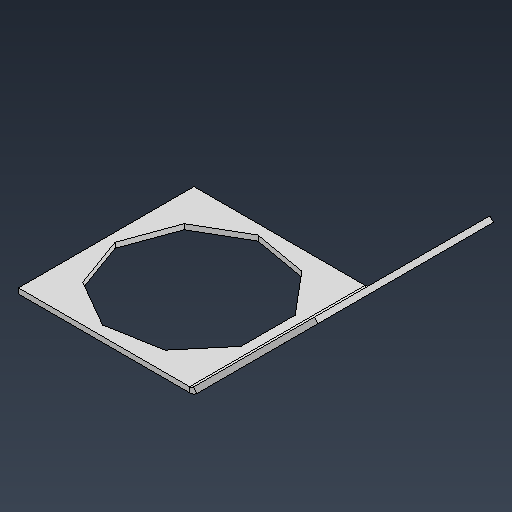
# Autodesk Inventor part: PROJECT_X.0002
Saved by Autodesk Inventor 2026 (Build 300175000, 175)
## iProperties
Manager: Летов
Company: ООО "МОЯ ОБОРОНА"
Created: 2026-10-15
Part Number: PROJECT_X.0002
Material: Типовые
Document SubType Name: Sheet Metal
Designer: dmitrii.kriskovets
Density: 1 g/cm^3
Sheet Metal Rule: По умолчанию_мм
Appearance: По умолчанию
Checked By: Летов
Engr Approved By: Летов
Mfg Approved By: Летов
Authority: Летов
Mass: 41.9969 g
Surface Area: 306.204 cm^2
Volume: 41.9969 cm^3
Flat Pattern Width: 10 cm
Flat Pattern Length: 19.8422 cm
Flat Pattern Area: 198.422 cm^2
Sheet Metal Width: 100,0 мм
Sheet Metal Length: 198,4 мм
Sheet Metal Area: 19842,2 мм^2
Author: Ивлев
Title: Деталь 1
Autodesk Inventor part; units mm, degrees
ref_plane "YZ Plane" through (0, 0, 0) normal (1, 0, 0) x (0, 1, 0)
ref_plane "XZ Plane" through (0, 0, 0) normal (0, 1, 0) x (-1, 0, 0)
ref_plane "XY Plane" through (0, 0, 0) normal (0, 0, 1) x (1, 0, 0)
sketch "Эскиз1" plane through (0, 0, 0) normal (0, 1, 0) x (-1, 0, 0)
  line L0 (-50, 50) -> (50, 50)
  line L1 (50, 50) -> (50, -50)
  line L2 (50, -50) -> (-50, -50)
  line L3 (-50, -50) -> (-50, 50)
  line L4 (-50, 50) -> (50, -50) construction
  line L5 (50, 50) -> (-50, -50) construction
  point P0 (0, 0)
  dimension "d0" = 100
  dimension "d1" = 100
  measures "d0" distance of L0.start L0.end
  measures "d1" distance of L0.end L1.end
extrude "Пластина1" add sketch "Эскиз1" along normal blind 3
sketch "Эскиз2" plane through (0, 3, 0) normal (0, 1, 0) x (1, 0, 0)
  line L0 (-50, -50) -> (-50, 50) construction
  line L1 (50, 50) -> (50, -50) construction
  line L2 (50, -50) -> (-50, -50) construction
  line L3 (-50, 50) -> (50, 50) construction
  line L4 (50, 0) -> (-50, 0)
  line L5 (-45, 0) -> (-34.472, 28.9254)
  line L6 (-34.472, 28.9254) -> (-7.8142, 44.3163)
  line L7 (-7.8142, 44.3163) -> (22.5, 38.9711)
  line L8 (22.5, 38.9711) -> (42.2862, 15.3909)
  line L9 (42.2862, 15.3909) -> (42.2862, -15.3909)
  line L10 (42.2862, -15.3909) -> (22.5, -38.9711)
  line L11 (22.5, -38.9711) -> (-7.8142, -44.3163)
  line L12 (-7.8142, -44.3163) -> (-34.472, -28.9254)
  line L13 (-34.472, -28.9254) -> (-45, 0)
  point P0 (0, 0)
  point P1 (0, 0)
  dimension "d3" = 5
  constraints: 20 end point, 3 midpoint, 1 coincident, 1 point on line, 19 other
  measures "d3" distance of point (-50, 0) L5.start
extrude "Выдавливание1" cut sketch "Эскиз2" against normal blind 10
sketch "Эскиз3" plane through (47.8787, 2.1213, -50) normal (0.7071068, -0.7071068, 0) x (0.7071068, 0.7071068, 0)
  line L0 (0, 100) -> (0, 0)
  line L1 (0, 0) -> (100, 0)
  line L2 (100, 0) -> (100, 100)
  line L3 (100, 100) -> (0, 100)
  constraints: 6 end point, 1 horizontal, 1 perpendicular, 1 vertical
edge flange "Фланец1" height 100 angle 45 thickness 3 bend radius 3 thickness toward (0.7071068, -0.7071068, 0) relief tear relief width 3 relief depth 1.5 edges at (50, 3, 0) wall of the first edge with corners at (47.8787, 2.1213, 50) (47.8787, 2.1213, -50) (118.5894, 72.832, -50) (118.5894, 72.832, 50)
bend "Сгиб1"
corner "УглСтык1"
equation "\"d0\" = a_1"
equation "\"d1\" = b_1"
equation "\"d2\" = Толщина"
equation "\"d6\" = Ширина_просечки"
equation "\"d7\" = Глубина_просечки"
equation "\"d8\" = Мин_остаток"
equation "\"d9\" = Радиус_перехода"
equation "\"d10\" = a_1"
equation "\"d11\" = alpha_1"
equation "\"d12\" = Радиус_гибки"
equation "\"d13\" = Размер_просечки"
equation "\"d14\" = Размер_зазора"
equation "\"d15\" = Радиус_Якоби"
equation "\"Толщина\" = c_1"
equation "\"Радиус_гибки\" = Толщина"
equation "\"Ширина_просечки\" = Толщина"
equation "\"Глубина_просечки\" = 0.5 * Толщина"
equation "\"Размер_просечки\" = 4 * Толщина"
equation "\"Мин_остаток\" = 2 * Толщина"
equation "\"Радиус_перехода\" = Радиус_гибки"
equation "\"Радиус_Якоби\" = Радиус_гибки"
equation "\"Размер_зазора\" = Толщина"
equation "\"alpha_1\" = 45deg"
equation "\"b_1\" = 100"
equation "\"c_1\" = 3"
equation "\"a_1\" = 100"
